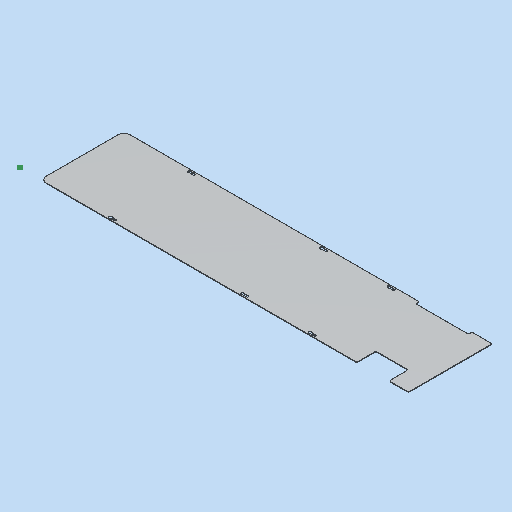
# Autodesk Inventor part: MM0948AN170_G01_104
Saved by Autodesk Inventor 2023.3 (Build 273359000, 359)
## iProperties
Part Number: MM0948AN170_G01_104
Material: 3.3535 AlMg3 - AW 5754 (Blech)
Description: =<RBPARTNOTITLE2>
Document SubType Name: Blech
Designer: Benutzer
Mass: 1872.56 g
Surface Area: 7009.08 cm^2
Volume: 693.796 cm^3
Density: 2.699 g/cm^3
Sheet Metal Rule: Standard_mm
Appearance: Aluminium AnP
Vendor: ASW
Created: 2023-03-23
RBCHANGEDESCRIPTION1: Erstfreigabe
RBCHANGENO1: 00
RBDOCUMENTTYPE: DRF
RBDOCUMENTVERSION: 00
RBDRAWINGMAINSCALE: 1:1
RBDRAWINGMISSINGSPEC: --
RBDRAWINGVOLUME: --
RBDSV1: 0850
RBGBDETAILS: 43274
RBGBEDGESIN1: +0,5
RBGBEDGESIN2: +0,2
RBGBEDGESOUT1: -0,3
RBGBEDGESOUT2: -0,1
RBMATERIAL: =<Material>
RBMATMEETS: --
RBMATNO: =<Part Number>
RBORGUNITRESPONSIBLE1: AnP/TEF1
RBPARTMADEOF: 2 x 285 x 1254 (FM)
RBPARTNO: SIEHE MNR
RBPARTNOTITLE1: manufactured part
RBPARTNOTITLE2: Anfertigungsteil
RBPARTSAFETYINDICATOR: --
RBSURFACE: anodised grey
RBSURFACE2: eloxiert E6/EV1 aluminiumfarbig
RBZEDGESNORM: ISO13715:2002-06
RBZGENDIMCLASS: m
RBZGENDIMNORM: ISO 2768-1:1989-11
RBZGENGEOCLASS: H
RBZGENGEONORM: ISO 2768-2:1989-11
RBZSURFACENORM: ISO13D2:2002-02
RBZTOLERANCENORM: ISO 14405-1:2010-12
AnP_Material: =<Material>
AnP_TemplVers: 20190222
AnP_Kategorie: 1
MaxAbmaße: 2 x 285 x 1254 (FM)
AnP_Kommentar_aktuell: =<Comments>
AnP_Material_aktuell: =<Material>
Author: FH/Wi
Keywords: =<RBPARTMADEOF>
Comments: =<RBSURFACE2>
Revision Number: 01
Autodesk Inventor part; units mm, degrees
ref_plane "YZ Plane" through (0, 0, 0) normal (1, 0, 0) x (0, 1, 0)
ref_plane "XZ Plane" through (0, 0, 0) normal (0, 1, 0) x (-1, 0, 0)
ref_plane "XY Plane" through (0, 0, 0) normal (0, 0, 1) x (1, 0, 0)
sketch "Skizze1" plane through (0, 0, 0) normal (0, 0, 1) x (1, 0, 0)
  line L0 (0, 0) -> (1300, 0)
  line L1 (1300, 0) -> (1300, 285)
  line L2 (1300, 285) -> (0, 285)
  line L3 (0, 285) -> (0, 0)
  dimension "d0" = 1300
  dimension "d1" = 285
  constraints: 8 end point, 2 parallel, 1 horizontal, 1 perpendicular
  measures "d0" distance of L2.end L1.end
  measures "d1" distance of L1.end L0.end
extrude "Extrusion1" add sketch "Skizze1" along normal blind 2
sketch "Skizze5" plane through (1300, 0, 0) normal (1, 0, 0) x (0, 0, -1)
  line L0 (0, 0) -> (0, 285) projected
  line L1 (0, 285) -> (-2, 285) projected
  line L2 (-2, 0) -> (-2, 285) projected
  line L3 (0, 0) -> (-2, 0) projected
extrude "Extrusion4" add sketch "Skizze5" along normal blind 24
sketch "Skizze9" plane through (0, 0, 2) normal (0, 0, 1) x (1, 0, 0)
  point P0 (0, 0)
sketch "Skizze14" plane through (0, 0, 2) normal (0, 0, 1) x (1, 0, 0)
  line L0 (1148, 65) -> (1258, 65)
  line L1 (1258, 65) -> (1258, 0)
  line L2 (1258, 0) -> (1148, 0)
  line L3 (1148, 0) -> (1148, 65)
  line L4 (1203, 285) -> (1203, 0) construction
  line L5 (1324, 285) -> (1324, 0) projected
  line L6 (0, 0) -> (1324, 0) projected
  dimension "d88" = 110
  dimension "d90" = 65
  dimension "d95" = 121
  constraints: 10 end point, 2 parallel, 1 horizontal, 1 midpoint, 1 perpendicular, 1 point on line
  measures "d88" distance of L0.start L0.end
  measures "d90" distance of L0.end L1.end
  measures "d95" distance between parallel lines of L5 L4
extrude "Ausklinkung1" cut sketch "Skizze14" against normal blind 2
sketch "Skizze10" plane through (0, 0, 2) normal (0, 0, 1) x (1, 0, 0)
  line L0 (0, 0) -> (1148, 0) projected
  line L1 (1324, 285) -> (1324, 0) projected
  line L2 (0, 285) -> (1324, 285) projected
  circle A0 centre (300.5, 277) radius 5
  line L3 (300.5, 277) -> (317.5, 277) construction
  line L4 (300.5, 274) -> (317.5, 274)
  line L5 (317.5, 280) -> (300.5, 280)
  arc A1 (300.5, 280) -> (300.5, 274) centre (300.5, 277) ccw
  arc A2 (317.5, 274) -> (317.5, 280) centre (317.5, 277) ccw
  line L6 (0, 342) -> (0, -57) projected
  circle A3 centre (300.5, 8) radius 5
  line L7 (300.5, 8) -> (317.5, 8) construction
  line L8 (300.5, 5) -> (317.5, 5)
  line L9 (317.5, 11) -> (300.5, 11)
  arc A4 (300.5, 11) -> (300.5, 5) centre (300.5, 8) ccw
  arc A5 (317.5, 5) -> (317.5, 11) centre (317.5, 8) ccw
  line L10 (0, 285) -> (0, 0) projected
  line L11 (1258, 65) -> (1258, 0) projected
  line L12 (1258, 0) -> (1324, 0) projected
  line L13 (1148, 0) -> (1148, 65) projected
  line L14 (1148, 65) -> (1258, 65) projected
  point P0 (309, 277)
  point P1 (309, 8)
  dimension "d53" = 10
  dimension "d54" = 17
  dimension "d55" = 6
  dimension "d56" = 8
  dimension "d58" = 309
  dimension "d64" = 10
  dimension "d65" = 17
  dimension "d66" = 6
  dimension "d67" = 269
  constraints: 16 end point, 8 point on circle, 8 tangent, 6 centre point, 2 horizontal, 2 midpoint, 2 parallel, 1 vertical alignment
  measures "d53" diameter of A0
  measures "d54" distance of L3.start L3.end
  measures "d55" diameter of A2
  measures "d56" distance from line of L2 point (309, 277)
  measures "d58" distance from line of point (309, 277) L6
  measures "d64" diameter of A3
  measures "d65" distance of L7.start L7.end
  measures "d66" diameter of A5
  measures "d67" distance of L3.start L7.start
extrude "Extrusion7" cut sketch "Skizze10" against normal through all contours A0 L4 A1 L5 | A0 L5 A2 L4 | L5 A1 L4 A0 | A3 L8 A4 L9 | A3 L9 A5 L8 | L9 A4 L8 A3
pattern_linear "Rechteckige Anordnung3" count 2 spacing 450 along (1, 0, 0) of "Extrusion7"
fillet "Rundung1" radius 5 8 edges at (0, 0, 1) (0, 285, 1) (1324, 0, 1) (1324, 285, 1) (1148, 65, 1) (1258, 65, 1) (1148, 0, 1) (1258, 0, 1)
sketch "Skizze12" plane through (0, 0, 2) normal (0, 0, 1) x (1, 0, 0)
  line L0 (0, 280) -> (0, 5) projected
  arc A0 (0, 5) -> (5, 0) centre (5, 5) ccw projected
  line L1 (5, 0) -> (1143, 0) projected
  arc A1 (1319, 0) -> (1324, 5) centre (1319, 5) ccw projected
  line L2 (1324, 280) -> (1324, 5) projected
  arc A2 (1324, 280) -> (1319, 285) centre (1319, 280) ccw projected
  line L3 (5, 285) -> (1319, 285) projected
  line L4 (754.5, 11) -> (767.5, 11) projected
  arc A3 (767.5, 5) -> (767.5, 11) centre (767.5, 8) ccw projected
  line L5 (767.5, 5) -> (754.5, 5) projected
  arc A4 (754.5, 11) -> (754.5, 5) centre (750.5, 8) ccw projected
  arc A5 (767.5, 274) -> (767.5, 280) centre (767.5, 277) ccw projected
  line L6 (767.5, 274) -> (754.5, 274) projected
  arc A6 (754.5, 280) -> (754.5, 274) centre (750.5, 277) ccw projected
  line L7 (754.5, 280) -> (767.5, 280) projected
  line L8 (317.5, 5) -> (304.5, 5) projected
  arc A7 (304.5, 11) -> (304.5, 5) centre (300.5, 8) ccw projected
  line L9 (304.5, 11) -> (317.5, 11) projected
  arc A8 (317.5, 5) -> (317.5, 11) centre (317.5, 8) ccw projected
  line L10 (0, 0) -> (70, 0)
  line L11 (70, 0) -> (70, 150)
  line L12 (70, 150) -> (0, 150)
  line L13 (0, 150) -> (0, 0)
  arc A9 (5, 285) -> (0, 280) centre (5, 280) ccw projected
  line L14 (1148, 5) -> (1148, 60) projected
  line L15 (1153, 65) -> (1253, 65) projected
  line L16 (1258, 60) -> (1258, 5) projected
  line L17 (1263, 0) -> (1319, 0) projected
  arc A10 (1153, 65) -> (1148, 60) centre (1153, 60) ccw projected
  arc A11 (1258, 60) -> (1253, 65) centre (1253, 60) ccw projected
  arc A12 (1258, 5) -> (1263, 0) centre (1263, 5) ccw projected
  arc A13 (1143, 0) -> (1148, 5) centre (1143, 5) ccw projected
  dimension "d80" = 70
  constraints: 8 end point, 2 parallel, 1 horizontal, 1 perpendicular
  measures "d80" distance between parallel lines of L0 L11
extrude "Extrusion9" cut sketch "Skizze12" against normal blind 10 contours L12 L11 L1 A0 L0
fillet "Rundung2" radius 20 1 edges at (70, 0, 1)
sketch "Skizze13" plane through (0, 150, 0) normal (-1, 0, 0) x (0, 0, 1)
  line L0 (2, -130) -> (0, -130) projected
  line L1 (2, 0) -> (2, -130) projected
  line L2 (2, 0) -> (0, 0) projected
  line L3 (0, -130) -> (0, 0) projected
  line L4 (0, -130) -> (0, -150) projected
  line L5 (0, -150) -> (2, -150) projected
  line L6 (2, -150) -> (2, -130) projected
  line L7 (2, -130) -> (0, -130) projected
  line L8 (0, 0) -> (2, 0) projected
  line L9 (2, 130) -> (2, 0) projected
  line L10 (0, 130) -> (2, 130) projected
  line L11 (0, 130) -> (0, 0) projected
  line L12 (2, 130) -> (2, 135) projected
  line L13 (2, 135) -> (0, 135) projected
  line L14 (0, 135) -> (0, 130) projected
  line L15 (0, 130) -> (2, 130) projected
extrude "Extrusion10" cut sketch "Skizze13" against normal up to surface (70 mm away) contours L2 L11 L10 L9 | L10 L14 L13 L12
fillet "Rundung4" radius 20 1 edges at (70, 285, 1)
pattern_linear "Rechteckige Anordnung4" count 2 spacing 680 along (1, 0, 0) of "Extrusion7"
sketch "Skizze15" plane through (25.5367, 2.1299, 2) normal (0, 0, 1) x (1, 0, 0)
  line L0 (90, -2.1299) -> (1319, -2.1299)
  line L1 (1229.4633, 282.8701) -> (1049.4633, 282.8701)
  line L2 (1049.4633, 282.8701) -> (1049.4633, 270.8701)
  line L3 (1049.4633, 270.8701) -> (1229.4633, 270.8701)
  line L4 (1229.4633, 270.8701) -> (1229.4633, 282.8701)
  line L5 (1298.4633, 277.8701) -> (1298.4633, 2.8701) projected
  line L6 (64.4633, 282.8701) -> (1293.4633, 282.8701) projected
  point P0 (0, 0)
  dimension "d104" = 180
  dimension "d106" = 69
  dimension "d107" = 12
  constraints: 10 end point, 2 parallel, 1 horizontal, 1 perpendicular, 1 point on line
  measures "d104" distance of L2.end L3.end
  measures "d106" distance between parallel lines of L5 L4
  measures "d107" distance of L3.end L1.start
extrude "Ausklinkung2" cut sketch "Skizze15" against normal blind 2
fillet "Eckenrundung1" radius 5 4 edges at (1075, 285, 1) (1075, 273, 1) (1255, 285, 1) (1255, 273, 1)
equation "\"d93\" = Stärke"
equation "\"d100\" = Stärke"
equation "\"Biegeradius\" = Stärke"
equation "\"BreiteBiegungsfreistellung\" = Stärke"
equation "\"TiefeBiegungsfreistellung\" = 0.5 * Stärke"
equation "\"GrößeEckenfreistellung\" = 4 * Stärke"
equation "\"MinimalRest\" = 2 * Stärke"
equation "\"Übergangsradius\" = Biegeradius"
equation "\"JacobiRadiusGröße\" = Biegeradius"
equation "\"Abstandsgröße\" = Stärke"
equation "\"d92\" = Stärke"
equation "\"d105\" = Stärke"
equation "\"Stärke\" = 2"
